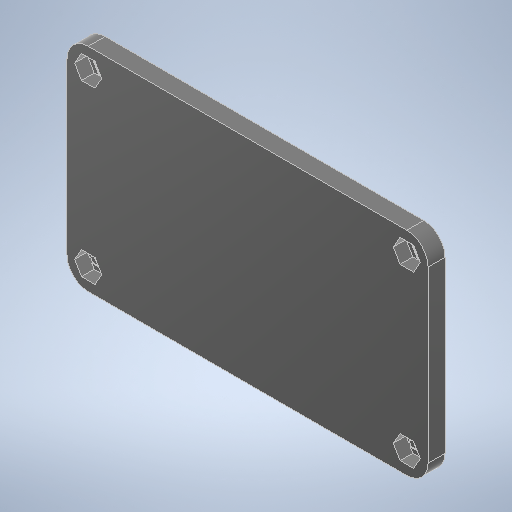
# Autodesk Inventor part: 3D_base
Saved by Autodesk Inventor 2025.3 (Build 293356030, 356C)
## iProperties
Created: 2026-02-13
Part Number: 3D_base
Material: 一般
Document SubType Name: Modeling
Designer: ibuki_ono
Density: 1 g/cm^3
Appearance: 滑らか - 黒
Author: ibuki_ono
## iProperties of the stored document 3D_base_3D プリント.ipt
Created: 2026-02-13
Part Number: 3D_base_3D プリント
Material: 一般
Document SubType Name: Modeling
Designer: ibuki_ono
Density: 1 g/cm^3
Appearance: 既定
Author: ibuki_ono
Autodesk Inventor part; units mm, degrees
ref_plane "YZ Plane" through (0, 0, 0) normal (1, 0, 0) x (0, 1, 0)
ref_plane "XZ Plane" through (0, 0, 0) normal (0, 1, 0) x (-1, 0, 0)
ref_plane "XY Plane" through (0, 0, 0) normal (0, 0, 1) x (1, 0, 0)
sketch "スケッチ1" plane through (0, 0, 0) normal (0, 0, 1) x (1, 0, 0)
  line L0 (-42.5, -25) -> (42.5, -25)
  line L1 (42.5, -25) -> (42.5, 25)
  line L2 (42.5, 25) -> (-42.5, 25)
  line L3 (-42.5, 25) -> (-42.5, -25)
  line L4 (-42.5, -25) -> (42.5, 25) construction
  line L5 (42.5, -25) -> (-42.5, 25) construction
  point P0 (0, 0)
  dimension "d0" = 85
  dimension "d1" = 50
  constraints: 12 end point, 2 midpoint, 2 parallel, 1 horizontal, 1 perpendicular
  measures "d0" distance of L2.end L1.end
  measures "d1" distance of L1.end L0.end
extrude "押し出し1" add sketch "スケッチ1" along normal blind 4
sketch "スケッチ2" plane through (0, 0, 4) normal (0, 0, 1) x (1, 0, 0)
  line L0 (-37.5, -20) -> (37.5, -20) construction
  line L1 (37.5, -20) -> (37.5, 20) construction
  line L2 (37.5, 20) -> (-37.5, 20) construction
  line L3 (-37.5, 20) -> (-37.5, -20) construction
  line L4 (-37.5, -20) -> (37.5, 20) construction
  line L5 (37.5, -20) -> (-37.5, 20) construction
  point P0 (0, 0)
  point P1 (-37.5, 20)
  dimension "d4" = 75
  dimension "d5" = 40
  constraints: 12 end point, 4 coincident, 2 midpoint, 2 parallel, 1 horizontal, 1 perpendicular
  measures "d4" distance of L2.end L1.end
  measures "d5" distance of L1.end L0.end
hole "穴1" at (-37.5, 20, 4) at (37.5, 20, 4) at (37.5, -20, 4) at (-37.5, -20, 4) direction (0, 0, -1) diameter 3.5 end through all
sketch "スケッチ3" plane through (0, 0, 4) normal (0, 0, 1) x (1, 0, 0)
  circle A0 centre (-37.5, 20) radius 1.75 projected
  line L0 (-40.6754, 20) -> (-39.0877, 22.75)
  line L1 (-39.0877, 22.75) -> (-35.9123, 22.75)
  line L2 (-35.9123, 22.75) -> (-34.3246, 20)
  line L3 (-34.3246, 20) -> (-35.9123, 17.25)
  line L4 (-35.9123, 17.25) -> (-39.0877, 17.25)
  line L5 (-39.0877, 17.25) -> (-40.6754, 20)
  point P0 (0, 0)
  dimension "d13" = 5.5
  constraints: 12 end point, 1 coincident, 1 horizontal alignment, 13 other
  measures "d13" distance between parallel lines of L4 L1
extrude "押し出し2" cut sketch "スケッチ3" against normal blind 3
sketch "スケッチ4" plane through (0, 0, 1) normal (0, 0, 1) x (1, 0, 0)
  line L0 (-35.9123, 17.25) -> (-39.0877, 17.25) projected
  line L1 (-34.3246, 20) -> (-35.9123, 17.25) projected
  line L2 (-35.9123, 22.75) -> (-34.3246, 20) projected
  line L3 (-39.0877, 22.75) -> (-35.9123, 22.75) projected
  line L4 (-40.6754, 20) -> (-39.0877, 22.75) projected
  line L5 (-39.0877, 17.25) -> (-40.6754, 20) projected
  circle A0 centre (-37.5, 20) radius 1.75 projected
  line L6 (-39.6651, 21.75) -> (-35.3349, 21.75)
  line L7 (-34.9019, 21) -> (-37.067, 17.25)
  line L8 (-35.9123, 17.25) -> (-39.0877, 17.25) projected
  line L9 (-37.933, 17.25) -> (-40.0981, 21)
  line L10 (-39.0877, 22.75) -> (-35.9123, 22.75) projected
  line L11 (-34.3246, 20) -> (-35.9123, 17.25) projected
  line L12 (-39.0877, 17.25) -> (-40.6754, 20) projected
  circle A1 centre (-37.5, 20) radius 1.75 projected
  point P0 (0, 0)
  point P1 (-39.0155, 19.125)
  point P2 (-35.9845, 19.125)
  point P3 (-37.5, 21.75)
  constraints: 6 end point, 6 point on line, 3 parallel, 3 tangent, 1 horizontal
extrude "押し出し3" cut sketch "スケッチ4" against normal blind 0.2 contours L0 L9 A0 L7 | A0 L6 L2 L7 | L9 L4 L6 A0
mirror "ミラー1" about plane through (0, 0, 0) normal (0, 1, 0) of "押し出し2", "押し出し3"
mirror "ミラー2" about plane through (0, 0, 0) normal (1, 0, 0) of "押し出し2", "押し出し3", "ミラー1"
sketch "スケッチ5" plane through (0, 0, 0) normal (0, 0, -1) x (-1, 0, 0)
  line L0 (-42.5, 25) -> (42.5, 25) projected
  line L1 (-42.5, -25) -> (-42.5, 25) projected
  line L2 (42.5, -25) -> (-42.5, -25) projected
  line L3 (42.5, 25) -> (42.5, -25) projected
  line L4 (41.5, 24) -> (-41.5, 24)
  line L5 (-41.5, 24) -> (-41.5, -24)
  line L6 (-41.5, -24) -> (41.5, -24)
  line L7 (41.5, -24) -> (41.5, 24)
  line L8 (-42.5, 25) -> (-32.5, 25)
  line L9 (-32.5, 25) -> (-32.5, 15)
  line L10 (-32.5, 15) -> (-42.5, 15)
  line L11 (-42.5, 15) -> (-42.5, 25)
  line L12 (42.5, 25) -> (32.5, 25)
  line L13 (32.5, 25) -> (32.5, 15)
  line L14 (32.5, 15) -> (42.5, 15)
  line L15 (42.5, 15) -> (42.5, 25)
  line L16 (42.5, -25) -> (32.5, -25)
  line L17 (32.5, -25) -> (32.5, -15)
  line L18 (32.5, -15) -> (42.5, -15)
  line L19 (42.5, -15) -> (42.5, -25)
  line L20 (-42.5, -25) -> (-32.5, -25)
  line L21 (-32.5, -25) -> (-32.5, -15)
  line L22 (-32.5, -15) -> (-42.5, -15)
  line L23 (-42.5, -15) -> (-42.5, -25)
  line L24 (-41.5, 0) -> (41.5, 0)
  point P0 (0, 0)
  point P1 (-41.5, -15)
  point P2 (-32.5, -24)
  point P3 (32.5, -24)
  point P4 (41.5, -15)
  dimension "d18" = 1
  dimension "d19" = 10
  dimension "d20" = 10
  dimension "d21" = 10
  dimension "d22" = 10
  dimension "d23" = 10
  dimension "d24" = 10
  dimension "d25" = 10
  dimension "d26" = 10
  constraints: 42 end point, 8 parallel, 4 horizontal, 4 perpendicular, 2 midpoint, 3 other
  measures "d18" distance between parallel lines of L0 L4
  measures "d19" distance of L9.end L10.end
  measures "d20" distance of L8.end L9.end
  measures "d21" distance of L14.end L13.end
  measures "d22" distance of L13.end L12.end
  measures "d23" distance of L17.end L18.end
  measures "d24" distance of L16.end L17.end
  measures "d25" distance of L22.end L21.end
  measures "d26" distance of L21.end L20.end
extrude "押し出し4" cut sketch "スケッチ5" against normal blind 3 contours L5 L24 L7 L18 L17 L6 L21 L22
mirror "ミラー3" about plane through (0, 0, 0) normal (0, 1, 0) of "押し出し4"
fillet "フィレット1" radius 4 12 edges at (32.5, -15, 1.5) (41.5, -15, 1.5) (32.5, -24, 1.5) (32.5, 15, 1.5) (32.5, 24, 1.5) (41.5, 15, 1.5) (-32.5, 24, 1.5) (-32.5, 15, 1.5) (-41.5, 15, 1.5) (-41.5, -15, 1.5) (-32.5, -15, 1.5) (-32.5, -24, 1.5)
chamfer "面取り1" distance 3 angle 45 16 edges at (0, -24, 3) (31.3284, -22.8284, 3) (32.5, -19.5, 3) (37, -15, 3) (40.3284, -13.8284, 3) (41.5, 0, 3) (37, 15, 3) (32.5, 19.5, 3) (0, 24, 3) (-32.5, 19.5, 3) (-37, 15, 3) (-41.5, 0, 3) (-40.3284, -13.8284, 3) (-37, -15, 3) (-32.5, -19.5, 3) (-31.3284, -22.8284, 3)
fillet "フィレット2" radius 5 4 edges at (-42.5, 25, 2) (-42.5, -25, 2) (42.5, 25, 2) (42.5, -25, 2)
